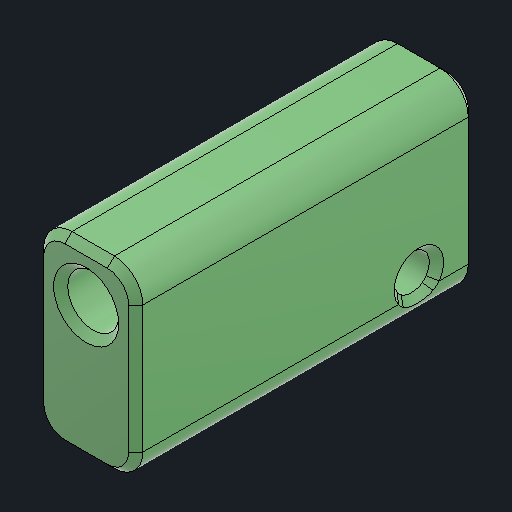
# Autodesk Inventor part: sensor-box-lower-mount-spacer
Saved by Autodesk Inventor 2027.1 (Build 311270010, 270A)
## iProperties
Created: 2026-10-26
Part Number: sensor-box-lower-mount-spacer
Material: ABS Plastic
Description: Sandwich M3 spacer with independent panel insert bosses; prototype
Document SubType Name: Modeling
Designer: queezz
Density: 1.06 g/cm^3
Appearance: Smooth - Dark Forest Green
Author: queezz
Autodesk Inventor part; units mm, degrees
ref_plane "XZ Plane" through (0, 0, 0) normal (0, 1, 0) x (-1, 0, 0)
ref_plane "XY Plane" through (0, 0, 0) normal (0, 0, 1) x (1, 0, 0)
sketch "Plain 7 x 13 mm block profile" plane through (0, 0, 0) normal (0, 0, 1) x (1, 0, 0)
  line L0 (-3.5, -9.5) -> (3.5, -9.5)
  line L1 (3.5, -9.5) -> (3.5, 3.5)
  line L2 (3.5, 3.5) -> (-3.5, 3.5)
  line L3 (-3.5, 3.5) -> (-3.5, -9.5)
  constraints: 8 end point, 2 parallel, 1 horizontal, 1 perpendicular
extrude "Plain rectangular spacer block" add sketch "Plain 7 x 13 mm block profile" along normal blind 24
sketch "Sandwich rod bore" plane through (0, 0, 0) normal (0, 0, 1) x (1, 0, 0)
  circle A0 centre (0, 0) radius 1.8
  dimension "d16" = 3.6
  constraints: 1 centre point
  measures "d16" diameter of A0
extrude "M3 sandwich rod clearance" cut sketch "Sandwich rod bore" along normal blind 24
ref_plane "Transverse insert pilot plane" through (3.5, 0, 0) normal (1, 0, 0) x (0, 1, 0)
sketch "Panel screw pilot" plane through (3.5, 0, 0) normal (1, 0, 0) x (0, 1, 0)
  circle A0 centre (-6.5, 4) radius 1.25
  dimension "d15" = 2.5
  constraints: 1 centre point
  measures "d15" diameter of A0
extrude "Straight M3 plastic screw pilot" cut sketch "Panel screw pilot" against normal blind 7
fillet "Fillet1" radius 2 4 edges at (3.5, -9.5, 12) (3.5, 3.5, 12) (-3.5, 3.5, 12) (-3.5, -9.5, 12)
chamfer "Chamfer1" distance 0.5 angle 45 16 edges at (-3.5, -3, 0) (-2.9142, -8.9142, 0) (0, -9.5, 0) (2.9142, -8.9142, 0) (3.5, -3, 0) (2.9142, 2.9142, 0) (0, 3.5, 0) (-2.9142, 2.9142, 0) (-3.5, -3, 24) (-2.9142, -8.9142, 24) (0, -9.5, 24) (2.9142, -8.9142, 24) (3.5, -3, 24) (2.9142, 2.9142, 24) (0, 3.5, 24) (-2.9142, 2.9142, 24)
chamfer "Chamfer2" distance 0.5 angle 45 8 edges at (3.5, -6.1047, 5.1859) (3.5, -6.1047, 2.8141) (3.4843, -7.75, 4) (-1.8, 0, 0) (-3.5, -6.1047, 2.8141) (-3.5, -6.1047, 5.1859) (-3.4843, -7.75, 4) (-1.8, 0, 24)
equation "\"d0\" = spacer_length"
equation "\"d16\" = rod_clearance"
equation "\"d4\" = spacer_length"
equation "\"d15\" = panel_screw_pilot"
equation "\"spacer_length\" = 24"
equation "\"rod_clearance\" = 3.6"
equation "\"panel_screw_pilot\" = 2.5"
body "Solid1"
